Autodesk Fusion 360 part; units mm, degrees
(part 2 of 7)
  spline S34 degree 5 poles (70.565, 33.8524) (70.5561, 33.8452) (70.5384, 33.8307) (70.5118, 33.8091) (70.4765, 33.7801) (70.4325, 33.7437) (70.3887, 33.7072) (70.3451, 33.6706) (70.3016, 33.6339) (70.2583, 33.597) (70.2152, 33.56) (70.1723, 33.5229) (70.1295, 33.4857) (70.087, 33.4483) (70.0446, 33.4108) (70.0024, 33.3732) (69.9604, 33.3355) (69.9186, 33.2976) (69.8769, 33.2596) (69.8355, 33.2214) (69.7942, 33.1832) (69.7532, 33.1448) (69.7123, 33.1063) (69.6717, 33.0676) (69.6312, 33.0288) (69.591, 32.9899) (69.5509, 32.9509) (69.5111, 32.9117) (69.4714, 32.8724) (69.432, 32.8329) (69.3928, 32.7934) (69.3538, 32.7536) (69.315, 32.7138) (69.2765, 32.6738) (69.2381, 32.6337) (69.2, 32.5934) (69.1621, 32.553) (69.1245, 32.5124) (69.0871, 32.4717) (69.0499, 32.4309) (69.013, 32.3899) (68.9763, 32.3488) (68.9399, 32.3075) (68.9037, 32.2661) (68.8678, 32.2245) (68.8321, 32.1828) (68.7967, 32.1409) (68.7616, 32.0989) (68.7268, 32.0567) (68.6922, 32.0143) (68.658, 31.9718) (68.624, 31.9292) (68.5903, 31.8863) (68.5569, 31.8433) (68.5239, 31.8001) (68.4945, 31.7612) (68.4718, 31.7308) (68.4558, 31.7091) (68.4462, 31.696) (68.4431, 31.6918) knots -1 -1 -1 -1 -1 -1 -0.985714 -0.971429 -0.957143 -0.942857 -0.928571 -0.914286 -0.9 -0.885714 -0.871429 -0.857143 -0.842857 -0.828571 -0.814286 -0.8 -0.785714 -0.771429 -0.757143 -0.742857 -0.728571 -0.714286 -0.7 -0.685714 -0.671429 -0.657143 -0.642857 -0.628571 -0.614286 -0.6 -0.585714 -0.571429 -0.557143 -0.542857 -0.528571 -0.514286 -0.5 -0.485714 -0.471429 -0.457143 -0.442857 -0.428571 -0.414286 -0.4 -0.385714 -0.371429 -0.357143 -0.342857 -0.328571 -0.314286 -0.3 -0.285714 -0.271429 -0.257143 -0.242857 -0.228571 -0.221564 -0.221564 -0.221564 -0.221564 -0.221564 -0.221564
  spline S35 degree 3 poles (67.845, 31.5267) (67.905, 31.5013) (67.9693, 31.4879) (68.0995, 31.4866) (68.1641, 31.4986) (68.268, 31.54) (68.3088, 31.5632) (68.3827, 31.6204) (68.4155, 31.6541) (68.4431, 31.6918) knots 0 0 0 0 0.019532 0.019532 0.039064 0.039064 0.053081 0.053081 0.067098 0.067098 0.067098 0.067098
  arc A18 (67.845, 31.5267) -> (67.3814, 31.7187) centre (54.5011, -0.0327) ccw
  spline S36 degree 3 poles (67.0752, 32.2584) (67.0652, 32.194) (67.068, 32.1283) (67.0984, 32.0017) (67.1259, 31.942) (67.1914, 31.8514) (67.2239, 31.8175) (67.2974, 31.7599) (67.3381, 31.7363) (67.3814, 31.7187) knots 0 0 0 0 0.019532 0.019532 0.039064 0.039064 0.053081 0.053081 0.067098 0.067098 0.067098 0.067098
  spline S37 degree 5 poles (67.0752, 32.2584) (67.076, 32.2636) (67.0784, 32.2796) (67.0825, 32.3063) (67.0879, 32.3438) (67.0947, 32.3921) (67.1018, 32.446) (67.1086, 32.5) (67.1151, 32.5542) (67.1213, 32.6084) (67.1271, 32.6627) (67.1326, 32.717) (67.1378, 32.7715) (67.1427, 32.8261) (67.1473, 32.8807) (67.1516, 32.9354) (67.1556, 32.9902) (67.1593, 33.0451) (67.1627, 33.1) (67.1658, 33.155) (67.1687, 33.2101) (67.1713, 33.2653) (67.1736, 33.3205) (67.1757, 33.3758) (67.1775, 33.4312) (67.179, 33.4866) (67.1803, 33.5421) (67.1813, 33.5976) (67.1821, 33.6532) (67.1826, 33.7089) (67.1828, 33.7646) (67.1829, 33.8204) (67.1826, 33.8762) (67.1822, 33.9321) (67.1814, 33.988) (67.1805, 34.044) (67.1793, 34.1) (67.1779, 34.1561) (67.1762, 34.2122) (67.1743, 34.2684) (67.1722, 34.3246) (67.1699, 34.3809) (67.1673, 34.4372) (67.1645, 34.4935) (67.1615, 34.5499) (67.1583, 34.6064) (67.1548, 34.6628) (67.1511, 34.7194) (67.1472, 34.7759) (67.1431, 34.8325) (67.1388, 34.8892) (67.1343, 34.9458) (67.1295, 35.0025) (67.1245, 35.0593) (67.1194, 35.1161) (67.114, 35.1729) (67.1095, 35.2183) (67.106, 35.2525) (67.1037, 35.2752) (67.1025, 35.2866) knots 0.221564 0.221564 0.221564 0.221564 0.221564 0.221564 0.228571 0.242857 0.257143 0.271429 0.285714 0.3 0.314286 0.328571 0.342857 0.357143 0.371429 0.385714 0.4 0.414286 0.428571 0.442857 0.457143 0.471429 0.485714 0.5 0.514286 0.528571 0.542857 0.557143 0.571429 0.585714 0.6 0.614286 0.628571 0.642857 0.657143 0.671429 0.685714 0.7 0.714286 0.728571 0.742857 0.757143 0.771429 0.785714 0.8 0.814286 0.828571 0.842857 0.857143 0.871429 0.885714 0.9 0.914286 0.928571 0.942857 0.957143 0.971429 0.985714 1 1 1 1 1 1
  arc A19 (67.1025, 35.2866) -> (66.0047, 35.6593) centre (54.5011, -0.0327) ccw
  spline S38 degree 5 poles (66.0047, 35.6593) (65.9968, 35.651) (65.9811, 35.6343) (65.9576, 35.6094) (65.9264, 35.576) (65.8875, 35.5342) (65.8488, 35.4923) (65.8104, 35.4503) (65.7721, 35.4082) (65.734, 35.366) (65.6961, 35.3237) (65.6583, 35.2813) (65.6208, 35.2388) (65.5835, 35.1962) (65.5464, 35.1535) (65.5094, 35.1107) (65.4727, 35.0678) (65.4362, 35.0248) (65.3999, 34.9817) (65.3638, 34.9385) (65.3279, 34.8952) (65.2922, 34.8518) (65.2567, 34.8082) (65.2214, 34.7646) (65.1864, 34.7209) (65.1515, 34.677) (65.1169, 34.6331) (65.0825, 34.5891) (65.0484, 34.5449) (65.0144, 34.5007) (64.9807, 34.4563) (64.9472, 34.4118) (64.914, 34.3672) (64.881, 34.3226) (64.8482, 34.2778) (64.8157, 34.2329) (64.7834, 34.1879) (64.7514, 34.1428) (64.7196, 34.0975) (64.6881, 34.0522) (64.6568, 34.0067) (64.6259, 33.9612) (64.5951, 33.9155) (64.5647, 33.8697) (64.5345, 33.8238) (64.5046, 33.7778) (64.4749, 33.7316) (64.4456, 33.6854) (64.4166, 33.639) (64.3878, 33.5925) (64.3594, 33.5459) (64.3313, 33.4991) (64.3035, 33.4523) (64.276, 33.4053) (64.2489, 33.3581) (64.2248, 33.3157) (64.2063, 33.2826) (64.1933, 33.259) (64.1855, 33.2448) (64.1829, 33.2401) knots -1 -1 -1 -1 -1 -1 -0.985714 -0.971429 -0.957143 -0.942857 -0.928571 -0.914286 -0.9 -0.885714 -0.871429 -0.857143 -0.842857 -0.828571 -0.814286 -0.8 -0.785714 -0.771429 -0.757143 -0.742857 -0.728571 -0.714286 -0.7 -0.685714 -0.671429 -0.657143 -0.642857 -0.628571 -0.614286 -0.6 -0.585714 -0.571429 -0.557143 -0.542857 -0.528571 -0.514286 -0.5 -0.485714 -0.471429 -0.457143 -0.442857 -0.428571 -0.414286 -0.4 -0.385714 -0.371429 -0.357143 -0.342857 -0.328571 -0.314286 -0.3 -0.285714 -0.271429 -0.257143 -0.242857 -0.228571 -0.221564 -0.221564 -0.221564 -0.221564 -0.221564 -0.221564
  spline S39 degree 3 poles (63.6115, 32.9984) (63.6743, 32.9811) (63.7398, 32.9762) (63.8691, 32.9919) (63.9316, 33.0122) (64.0292, 33.0668) (64.0666, 33.0952) (64.1324, 33.1615) (64.1605, 33.1992) (64.1829, 33.2401) knots 0 0 0 0 0.019532 0.019532 0.039064 0.039064 0.053081 0.053081 0.067098 0.067098 0.067098 0.067098
  arc A20 (63.6115, 32.9984) -> (63.1268, 33.1283) centre (54.5011, -0.0327) ccw
  spline S40 degree 3 poles (62.7528, 33.6234) (62.7513, 33.5583) (62.7626, 33.4935) (62.8093, 33.372) (62.8443, 33.3164) (62.9211, 33.235) (62.9578, 33.2057) (63.0382, 33.1581) (63.0816, 33.1401) (63.1268, 33.1283) knots 0 0 0 0 0.019532 0.019532 0.039064 0.039064 0.053081 0.053081 0.067098 0.067098 0.067098 0.067098
  spline S41 degree 5 poles (62.7528, 33.6234) (62.7529, 33.6287) (62.7532, 33.6448) (62.7537, 33.6718) (62.7543, 33.7097) (62.7546, 33.7585) (62.7547, 33.8129) (62.7544, 33.8673) (62.7538, 33.9218) (62.7528, 33.9764) (62.7515, 34.031) (62.7498, 34.0856) (62.7479, 34.1403) (62.7456, 34.195) (62.743, 34.2498) (62.7401, 34.3046) (62.737, 34.3594) (62.7335, 34.4143) (62.7297, 34.4692) (62.7256, 34.5242) (62.7213, 34.5792) (62.7167, 34.6342) (62.7117, 34.6893) (62.7066, 34.7444) (62.7011, 34.7995) (62.6954, 34.8546) (62.6894, 34.9098) (62.6832, 34.965) (62.6767, 35.0202) (62.6699, 35.0755) (62.6629, 35.1307) (62.6556, 35.186) (62.6481, 35.2414) (62.6404, 35.2967) (62.6324, 35.3521) (62.6241, 35.4074) (62.6156, 35.4628) (62.6069, 35.5182) (62.5979, 35.5737) (62.5887, 35.6291) (62.5793, 35.6846) (62.5696, 35.7401) (62.5597, 35.7956) (62.5496, 35.8511) (62.5393, 35.9066) (62.5287, 35.9621) (62.5179, 36.0177) (62.5069, 36.0732) (62.4956, 36.1288) (62.4842, 36.1844) (62.4725, 36.24) (62.4606, 36.2955) (62.4484, 36.3511) (62.4361, 36.4068) (62.4236, 36.4624) (62.4108, 36.518) (62.4004, 36.5625) (62.3926, 36.5959) (62.3873, 36.6181) (62.3846, 36.6293) knots 0.221564 0.221564 0.221564 0.221564 0.221564 0.221564 0.228571 0.242857 0.257143 0.271429 0.285714 0.3 0.314286 0.328571 0.342857 0.357143 0.371429 0.385714 0.4 0.414286 0.428571 0.442857 0.457143 0.471429 0.485714 0.5 0.514286 0.528571 0.542857 0.557143 0.571429 0.585714 0.6 0.614286 0.628571 0.642857 0.657143 0.671429 0.685714 0.7 0.714286 0.728571 0.742857 0.757143 0.771429 0.785714 0.8 0.814286 0.828571 0.842857 0.857143 0.871429 0.885714 0.9 0.914286 0.928571 0.942857 0.957143 0.971429 0.985714 1 1 1 1 1 1
  arc A21 (62.3846, 36.6293) -> (61.2476, 36.8554) centre (54.5011, -0.0327) ccw
  spline S42 degree 5 poles (61.2476, 36.8554) (61.2408, 36.8462) (61.2274, 36.8276) (61.2074, 36.7998) (61.1808, 36.7627) (61.1477, 36.7162) (61.1148, 36.6696) (61.0821, 36.6229) (61.0497, 36.5762) (61.0174, 36.5294) (60.9853, 36.4825) (60.9535, 36.4355) (60.9218, 36.3885) (60.8904, 36.3414) (60.8591, 36.2942) (60.8281, 36.247) (60.7973, 36.1996) (60.7667, 36.1522) (60.7363, 36.1047) (60.7062, 36.0572) (60.6762, 36.0095) (60.6465, 35.9618) (60.617, 35.9141) (60.5877, 35.8662) (60.5587, 35.8183) (60.5299, 35.7703) (60.5013, 35.7222) (60.473, 35.674) (60.4449, 35.6258) (60.417, 35.5775) (60.3894, 35.5291) (60.362, 35.4806) (60.3348, 35.4321) (60.3079, 35.3835) (60.2813, 35.3348) (60.2549, 35.2861) (60.2288, 35.2372) (60.2029, 35.1883) (60.1773, 35.1393) (60.152, 35.0903) (60.1269, 35.0411) (60.1021, 34.9919) (60.0776, 34.9426) (60.0534, 34.8932) (60.0295, 34.8438) (60.0058, 34.7942) (59.9825, 34.7446) (59.9594, 34.6949) (59.9367, 34.6452) (59.9143, 34.5953) (59.8922, 34.5454) (59.8704, 34.4954) (59.849, 34.4453) (59.8279, 34.3951) (59.8071, 34.3448) (59.7888, 34.2996) (59.7748, 34.2644) (59.7649, 34.2392) (59.759, 34.2242) (59.7571, 34.2192) knots -1 -1 -1 -1 -1 -1 -0.985714 -0.971429 -0.957143 -0.942857 -0.928571 -0.914286 -0.9 -0.885714 -0.871429 -0.857143 -0.842857 -0.828571 -0.814286 -0.8 -0.785714 -0.771429 -0.757143 -0.742857 -0.728571 -0.714286 -0.7 -0.685714 -0.671429 -0.657143 -0.642857 -0.628571 -0.614286 -0.6 -0.585714 -0.571429 -0.557143 -0.542857 -0.528571 -0.514286 -0.5 -0.485714 -0.471429 -0.457143 -0.442857 -0.428571 -0.414286 -0.4 -0.385714 -0.371429 -0.357143 -0.342857 -0.328571 -0.314286 -0.3 -0.285714 -0.271429 -0.257143 -0.242857 -0.228571 -0.221564 -0.221564 -0.221564 -0.221564 -0.221564 -0.221564
  spline S43 degree 3 poles (59.2221, 33.905) (59.2866, 33.896) (59.3522, 33.8997) (59.4784, 33.9321) (59.5377, 33.9605) (59.6273, 34.0273) (59.6607, 34.0603) (59.7173, 34.1347) (59.7402, 34.1757) (59.7571, 34.2192) knots 0 0 0 0 0.019532 0.019532 0.039064 0.039064 0.053081 0.053081 0.067098 0.067098 0.067098 0.067098
  arc A22 (59.2221, 33.905) -> (58.7246, 33.9705) centre (54.5011, -0.0327) ccw
  spline S44 degree 3 poles (58.2892, 34.4125) (58.2962, 34.3478) (58.3159, 34.285) (58.3781, 34.1706) (58.42, 34.1201) (58.5068, 34.0495) (58.547, 34.0252) (58.6329, 33.9885) (58.6782, 33.9763) (58.7246, 33.9705) knots 0 0 0 0 0.019532 0.019532 0.039064 0.039064 0.053081 0.053081 0.067098 0.067098 0.067098 0.067098
  spline S45 degree 5 poles (58.2892, 34.4125) (58.2886, 34.4178) (58.2868, 34.4338) (58.2838, 34.4607) (58.2794, 34.4983) (58.2734, 34.5467) (58.2663, 34.6007) (58.2589, 34.6546) (58.2512, 34.7085) (58.2431, 34.7625) (58.2347, 34.8164) (58.2259, 34.8704) (58.2169, 34.9244) (58.2075, 34.9783) (58.1978, 35.0323) (58.1877, 35.0862) (58.1774, 35.1402) (58.1668, 35.1942) (58.1559, 35.2481) (58.1447, 35.3021) (58.1332, 35.356) (58.1214, 35.41) (58.1094, 35.4639) (58.0971, 35.5179) (58.0845, 35.5718) (58.0716, 35.6257) (58.0585, 35.6797) (58.0451, 35.7336) (58.0314, 35.7875) (58.0175, 35.8414) (58.0033, 35.8952) (57.9889, 35.9491) (57.9742, 36.003) (57.9593, 36.0568) (57.9442, 36.1107) (57.9288, 36.1645) (57.9131, 36.2183) (57.8972, 36.2721) (57.8811, 36.3259) (57.8647, 36.3797) (57.8482, 36.4334) (57.8313, 36.4872) (57.8143, 36.5409) (57.797, 36.5946) (57.7795, 36.6483) (57.7617, 36.702) (57.7438, 36.7557) (57.7256, 36.8093) (57.7072, 36.8629) (57.6886, 36.9165) (57.6697, 36.9701) (57.6507, 37.0237) (57.6314, 37.0772) (57.6119, 37.1307) (57.5922, 37.1842) (57.5723, 37.2377) (57.5562, 37.2805) (57.5441, 37.3126) (57.5359, 37.3339) (57.5318, 37.3446) knots 0.221564 0.221564 0.221564 0.221564 0.221564 0.221564 0.228571 0.242857 0.257143 0.271429 0.285714 0.3 0.314286 0.328571 0.342857 0.357143 0.371429 0.385714 0.4 0.414286 0.428571 0.442857 0.457143 0.471429 0.485714 0.5 0.514286 0.528571 0.542857 0.557143 0.571429 0.585714 0.6 0.614286 0.628571 0.642857 0.657143 0.671429 0.685714 0.7 0.714286 0.728571 0.742857 0.757143 0.771429 0.785714 0.8 0.814286 0.828571 0.842857 0.857143 0.871429 0.885714 0.9 0.914286 0.928571 0.942857 0.957143 0.971429 0.985714 1 1 1 1 1 1
  arc A23 (57.5318, 37.3446) -> (56.375, 37.4204) centre (54.5011, -0.0327) ccw
  spline S46 degree 5 poles (56.375, 37.4204) (56.3695, 37.4104) (56.3586, 37.3903) (56.3424, 37.3601) (56.3209, 37.3198) (56.2941, 37.2693) (56.2676, 37.2189) (56.2413, 37.1683) (56.2152, 37.1178) (56.1893, 37.0671) (56.1637, 37.0165) (56.1382, 36.9658) (56.113, 36.915) (56.0879, 36.8642) (56.0631, 36.8133) (56.0385, 36.7624) (56.0142, 36.7115) (55.99, 36.6605) (55.9661, 36.6094) (55.9424, 36.5584) (55.9189, 36.5072) (55.8957, 36.456) (55.8727, 36.4048) (55.8499, 36.3535) (55.8274, 36.3022) (55.8051, 36.2509) (55.783, 36.1995) (55.7612, 36.148) (55.7396, 36.0965) (55.7183, 36.045) (55.6972, 35.9934) (55.6764, 35.9418) (55.6558, 35.8902) (55.6355, 35.8385) (55.6155, 35.7867) (55.5957, 35.7349) (55.5761, 35.6831) (55.5569, 35.6312) (55.5379, 35.5793) (55.5192, 35.5274) (55.5007, 35.4754) (55.4826, 35.4233) (55.4647, 35.3713) (55.4472, 35.3192) (55.4299, 35.267) (55.4129, 35.2148) (55.3962, 35.1626) (55.3799, 35.1103) (55.3638, 35.058) (55.3481, 35.0056) (55.3327, 34.9532) (55.3177, 34.9008) (55.3029, 34.8483) (55.2886, 34.7958) (55.2745, 34.7433) (55.2623, 34.6961) (55.253, 34.6593) (55.2465, 34.6331) (55.2426, 34.6174) (55.2414, 34.6122) knots -1 -1 -1 -1 -1 -1 -0.985714 -0.971429 -0.957143 -0.942857 -0.928571 -0.914286 -0.9 -0.885714 -0.871429 -0.857143 -0.842857 -0.828571 -0.814286 -0.8 -0.785714 -0.771429 -0.757143 -0.742857 -0.728571 -0.714286 -0.7 -0.685714 -0.671429 -0.657143 -0.642857 -0.628571 -0.614286 -0.6 -0.585714 -0.571429 -0.557143 -0.542857 -0.528571 -0.514286 -0.5 -0.485714 -0.471429 -0.457143 -0.442857 -0.428571 -0.414286 -0.4 -0.385714 -0.371429 -0.357143 -0.342857 -0.328571 -0.314286 -0.3 -0.285714 -0.271429 -0.257143 -0.242857 -0.228571 -0.221564 -0.221564 -0.221564 -0.221564 -0.221564 -0.221564
  spline S47 degree 3 poles (54.752, 34.2309) (54.8171, 34.2304) (54.8817, 34.2426) (55.0025, 34.2912) (55.0576, 34.327) (55.1378, 34.405) (55.1665, 34.4421) (55.2129, 34.5232) (55.2303, 34.5669) (55.2414, 34.6122) knots 0 0 0 0 0.019532 0.019532 0.039064 0.039064 0.053081 0.053081 0.067098 0.067098 0.067098 0.067098
  arc A24 (54.752, 34.2309) -> (54.2502, 34.2309) centre (54.5011, -0.0327) ccw
  spline S48 degree 3 poles (53.7608, 34.6122) (53.7762, 34.549) (53.8039, 34.4894) (53.8805, 34.3841) (53.9287, 34.3394) (54.0239, 34.2807) (54.0669, 34.2619) (54.1569, 34.2367) (54.2034, 34.2305) (54.2502, 34.2309) knots 0 0 0 0 0.019532 0.019532 0.039064 0.039064 0.053081 0.053081 0.067098 0.067098 0.067098 0.067098
  spline S49 degree 5 poles (53.7608, 34.6122) (53.7595, 34.6174) (53.7557, 34.6331) (53.7492, 34.6593) (53.7399, 34.6961) (53.7276, 34.7433) (53.7136, 34.7958) (53.6992, 34.8483) (53.6845, 34.9008) (53.6694, 34.9532) (53.654, 35.0056) (53.6383, 35.058) (53.6223, 35.1103) (53.6059, 35.1626) (53.5892, 35.2148) (53.5723, 35.267) (53.555, 35.3192) (53.5374, 35.3713) (53.5195, 35.4233) (53.5014, 35.4754) (53.483, 35.5274) (53.4643, 35.5793) (53.4453, 35.6312) (53.426, 35.6831) (53.4065, 35.7349) (53.3867, 35.7867) (53.3666, 35.8385) (53.3463, 35.8902) (53.3257, 35.9418) (53.3049, 35.9934) (53.2838, 36.045) (53.2625, 36.0965) (53.2409, 36.148) (53.2191, 36.1995) (53.1971, 36.2509) (53.1748, 36.3022) (53.1522, 36.3535) (53.1294, 36.4048) (53.1064, 36.456) (53.0832, 36.5072) (53.0597, 36.5584) (53.036, 36.6094) (53.0121, 36.6605) (52.988, 36.7115) (52.9636, 36.7624) (52.939, 36.8133) (52.9142, 36.8642) (52.8892, 36.915) (52.8639, 36.9658) (52.8385, 37.0165) (52.8128, 37.0671) (52.7869, 37.1178) (52.7608, 37.1683) (52.7345, 37.2189) (52.708, 37.2693) (52.6813, 37.3198) (52.6597, 37.3601) (52.6435, 37.3903) (52.6326, 37.4104) (52.6272, 37.4204) knots 0.221564 0.221564 0.221564 0.221564 0.221564 0.221564 0.228571 0.242857 0.257143 0.271429 0.285714 0.3 0.314286 0.328571 0.342857 0.357143 0.371429 0.385714 0.4 0.414286 0.428571 0.442857 0.457143 0.471429 0.485714 0.5 0.514286 0.528571 0.542857 0.557143 0.571429 0.585714 0.6 0.614286 0.628571 0.642857 0.657143 0.671429 0.685714 0.7 0.714286 0.728571 0.742857 0.757143 0.771429 0.785714 0.8 0.814286 0.828571 0.842857 0.857143 0.871429 0.885714 0.9 0.914286 0.928571 0.942857 0.957143 0.971429 0.985714 1 1 1 1 1 1
  arc A25 (52.6272, 37.4204) -> (51.4703, 37.3446) centre (54.5011, -0.0327) ccw
  spline S50 degree 5 poles (51.4703, 37.3446) (51.4662, 37.3339) (51.4581, 37.3126) (51.4459, 37.2805) (51.4298, 37.2377) (51.4099, 37.1842) (51.3902, 37.1307) (51.3707, 37.0772) (51.3515, 37.0237) (51.3324, 36.9701) (51.3136, 36.9165) (51.2949, 36.8629) (51.2765, 36.8093) (51.2584, 36.7557) (51.2404, 36.702) (51.2227, 36.6483) (51.2052, 36.5946) (51.1879, 36.5409) (51.1708, 36.4872) (51.154, 36.4334) (51.1374, 36.3797) (51.121, 36.3259) (51.1049, 36.2721) (51.089, 36.2183) (51.0734, 36.1645) (51.058, 36.1107) (51.0428, 36.0568) (51.0279, 36.003) (51.0132, 35.9491) (50.9988, 35.8952) (50.9846, 35.8414) (50.9707, 35.7875) (50.9571, 35.7336) (50.9437, 35.6797) (50.9306, 35.6257) (50.9177, 35.5718) (50.9051, 35.5179) (50.8928, 35.4639) (50.8807, 35.41) (50.8689, 35.356) (50.8575, 35.3021) (50.8463, 35.2481) (50.8353, 35.1942) (50.8247, 35.1402) (50.8144, 35.0862) (50.8044, 35.0323) (50.7947, 34.9783) (50.7853, 34.9244) (50.7762, 34.8704) (50.7675, 34.8164) (50.759, 34.7625) (50.7509, 34.7085) (50.7432, 34.6546) (50.7358, 34.6007) (50.7287, 34.5467) (50.7228, 34.4983) (50.7183, 34.4607) (50.7153, 34.4338) (50.7135, 34.4178) (50.713, 34.4125) knots -1 -1 -1 -1 -1 -1 -0.985714 -0.971429 -0.957143 -0.942857 -0.928571 -0.914286 -0.9 -0.885714 -0.871429 -0.857143 -0.842857 -0.828571 -0.814286 -0.8 -0.785714 -0.771429 -0.757143 -0.742857 -0.728571 -0.714286 -0.7 -0.685714 -0.671429 -0.657143 -0.642857 -0.628571 -0.614286 -0.6 -0.585714 -0.571429 -0.557143 -0.542857 -0.528571 -0.514286 -0.5 -0.485714 -0.471429 -0.457143 -0.442857 -0.428571 -0.414286 -0.4 -0.385714 -0.371429 -0.357143 -0.342857 -0.328571 -0.314286 -0.3 -0.285714 -0.271429 -0.257143 -0.242857 -0.228571 -0.221564 -0.221564 -0.221564 -0.221564 -0.221564 -0.221564
  spline S51 degree 3 poles (50.2775, 33.9705) (50.3422, 33.9785) (50.4046, 33.9991) (50.518, 34.063) (50.568, 34.1057) (50.6373, 34.1935) (50.661, 34.234) (50.6964, 34.3205) (50.7079, 34.366) (50.713, 34.4125) knots 0 0 0 0 0.019532 0.019532 0.039064 0.039064 0.053081 0.053081 0.067098 0.067098 0.067098 0.067098
  arc A26 (50.2775, 33.9705) -> (49.78, 33.905) centre (54.5011, -0.0327) ccw
  spline S52 degree 3 poles (49.245, 34.2192) (49.2686, 34.1585) (49.3038, 34.103) (49.3935, 34.0086) (49.4471, 33.9706) (49.5492, 33.9249) (49.5943, 33.9118) (49.6868, 33.8986) (49.7337, 33.8986) (49.78, 33.905) knots 0 0 0 0 0.019532 0.019532 0.039064 0.039064 0.053081 0.053081 0.067098 0.067098 0.067098 0.067098
  spline S53 degree 5 poles (49.245, 34.2192) (49.2431, 34.2242) (49.2372, 34.2392) (49.2274, 34.2644) (49.2134, 34.2996) (49.195, 34.3448) (49.1743, 34.3951) (49.1532, 34.4453) (49.1317, 34.4954) (49.1099, 34.5454) (49.0878, 34.5953) (49.0654, 34.6452) (49.0427, 34.6949) (49.0197, 34.7446) (48.9963, 34.7942) (48.9727, 34.8438) (48.9487, 34.8932) (48.9245, 34.9426) (48.9, 34.9919) (48.8752, 35.0411) (48.8502, 35.0903) (48.8248, 35.1393) (48.7992, 35.1883) (48.7734, 35.2372) (48.7472, 35.2861) (48.7208, 35.3348) (48.6942, 35.3835) (48.6673, 35.4321) (48.6402, 35.4806) (48.6128, 35.5291) (48.5852, 35.5775) (48.5573, 35.6258) (48.5292, 35.674) (48.5008, 35.7222) (48.4723, 35.7703) (48.4434, 35.8183) (48.4144, 35.8662) (48.3851, 35.9141) (48.3556, 35.9618) (48.3259, 36.0095) (48.296, 36.0572) (48.2658, 36.1047) (48.2354, 36.1522) (48.2048, 36.1996) (48.174, 36.247) (48.143, 36.2942) (48.1118, 36.3414) (48.0803, 36.3885) (48.0487, 36.4355) (48.0168, 36.4825) (47.9847, 36.5294) (47.9525, 36.5762) (47.92, 36.6229) (47.8873, 36.6696) (47.8544, 36.7162) (47.8214, 36.7627) (47.7948, 36.7998) (47.7747, 36.8276) (47.7613, 36.8462) (47.7546, 36.8554) knots 0.221564 0.221564 0.221564 0.221564 0.221564 0.221564 0.228571 0.242857 0.257143 0.271429 0.285714 0.3 0.314286 0.328571 0.342857 0.357143 0.371429 0.385714 0.4 0.414286 0.428571 0.442857 0.457143 0.471429 0.485714 0.5 0.514286 0.528571 0.542857 0.557143 0.571429 0.585714 0.6 0.614286 0.628571 0.642857 0.657143 0.671429 0.685714 0.7 0.714286 0.728571 0.742857 0.757143 0.771429 0.785714 0.8 0.814286 0.828571 0.842857 0.857143 0.871429 0.885714 0.9 0.914286 0.928571 0.942857 0.957143 0.971429 0.985714 1 1 1 1 1 1
  arc A27 (47.7546, 36.8554) -> (46.6175, 36.6293) centre (54.5011, -0.0327) ccw
  spline S54 degree 5 poles (46.6175, 36.6293) (46.6149, 36.6181) (46.6096, 36.5959) (46.6017, 36.5625) (46.5913, 36.518) (46.5786, 36.4624) (46.566, 36.4068) (46.5537, 36.3511) (46.5416, 36.2955) (46.5297, 36.24) (46.518, 36.1844) (46.5065, 36.1288) (46.4953, 36.0732) (46.4843, 36.0177) (46.4735, 35.9621) (46.4629, 35.9066) (46.4525, 35.8511) (46.4424, 35.7956) (46.4325, 35.7401) (46.4228, 35.6846) (46.4134, 35.6291) (46.4042, 35.5737) (46.3952, 35.5182) (46.3865, 35.4628) (46.378, 35.4074) (46.3698, 35.3521) (46.3618, 35.2967) (46.354, 35.2414) (46.3465, 35.186) (46.3392, 35.1307) (46.3322, 35.0755) (46.3255, 35.0202) (46.319, 34.965) (46.3127, 34.9098) (46.3067, 34.8546) (46.301, 34.7995) (46.2956, 34.7444) (46.2904, 34.6893) (46.2855, 34.6342) (46.2809, 34.5792) (46.2765, 34.5242) (46.2725, 34.4692) (46.2687, 34.4143) (46.2652, 34.3594) (46.262, 34.3046) (46.2591, 34.2498) (46.2565, 34.195) (46.2543, 34.1403) (46.2523, 34.0856) (46.2507, 34.031) (46.2494, 33.9764) (46.2484, 33.9218) (46.2477, 33.8673) (46.2474, 33.8129) (46.2475, 33.7585) (46.2479, 33.7097) (46.2484, 33.6718) (46.2489, 33.6448) (46.2493, 33.6287) (46.2494, 33.6234) knots -1 -1 -1 -1 -1 -1 -0.985714 -0.971429 -0.957143 -0.942857 -0.928571 -0.914286 -0.9 -0.885714 -0.871429 -0.857143 -0.842857 -0.828571 -0.814286 -0.8 -0.785714 -0.771429 -0.757143 -0.742857 -0.728571 -0.714286 -0.7 -0.685714 -0.671429 -0.657143 -0.642857 -0.628571 -0.614286 -0.6 -0.585714 -0.571429 -0.557143 -0.542857 -0.528571 -0.514286 -0.5 -0.485714 -0.471429 -0.457143 -0.442857 -0.428571 -0.414286 -0.4 -0.385714 -0.371429 -0.357143 -0.342857 -0.328571 -0.314286 -0.3 -0.285714 -0.271429 -0.257143 -0.242857 -0.228571 -0.221564 -0.221564 -0.221564 -0.221564 -0.221564 -0.221564
  spline S55 degree 3 poles (45.8754, 33.1283) (45.9384, 33.1447) (45.9976, 33.1732) (46.1017, 33.2514) (46.1457, 33.3003) (46.2029, 33.3964) (46.2211, 33.4397) (46.2449, 33.53) (46.2504, 33.5766) (46.2494, 33.6234) knots 0 0 0 0 0.019532 0.019532 0.039064 0.039064 0.053081 0.053081 0.067098 0.067098 0.067098 0.067098
  arc A28 (45.8754, 33.1283) -> (45.3906, 32.9984) centre (54.5011, -0.0327) ccw
  spline S56 degree 3 poles (44.8192, 33.2401) (44.8505, 33.1831) (44.8927, 33.1326) (44.9939, 33.0507) (45.052, 33.0201) (45.1592, 32.988) (45.2056, 32.981) (45.299, 32.98) (45.3456, 32.986) (45.3906, 32.9984) knots 0 0 0 0 0.019532 0.019532 0.039064 0.039064 0.053081 0.053081 0.067098 0.067098 0.067098 0.067098
  spline S57 degree 5 poles (44.8192, 33.2401) (44.8167, 33.2448) (44.8089, 33.259) (44.7958, 33.2826) (44.7773, 33.3157) (44.7533, 33.3581) (44.7261, 33.4053) (44.6986, 33.4523) (44.6708, 33.4991) (44.6427, 33.5459) (44.6143, 33.5925) (44.5856, 33.639) (44.5565, 33.6854) (44.5272, 33.7316) (44.4976, 33.7778) (44.4677, 33.8238) (44.4375, 33.8697) (44.407, 33.9155) (44.3763, 33.9612) (44.3453, 34.0067) (44.314, 34.0522) (44.2825, 34.0975) (44.2507, 34.1428) (44.2187, 34.1879) (44.1864, 34.2329) (44.1539, 34.2778) (44.1211, 34.3226) (44.0881, 34.3672) (44.0549, 34.4118) (44.0214, 34.4563) (43.9877, 34.5007) (43.9538, 34.5449) (43.9196, 34.5891) (43.8852, 34.6331) (43.8506, 34.677) (43.8158, 34.7209) (43.7807, 34.7646) (43.7455, 34.8082) (43.71, 34.8518) (43.6743, 34.8952) (43.6384, 34.9385) (43.6023, 34.9817) (43.566, 35.0248) (43.5294, 35.0678) (43.4927, 35.1107) (43.4558, 35.1535) (43.4187, 35.1962) (43.3813, 35.2388) (43.3438, 35.2813) (43.3061, 35.3237) (43.2682, 35.366) (43.2301, 35.4082) (43.1918, 35.4503) (43.1533, 35.4923) (43.1146, 35.5342) (43.0758, 35.576) (43.0445, 35.6094) (43.021, 35.6343) (43.0053, 35.651) (42.9974, 35.6593) knots 0.221564 0.221564 0.221564 0.221564 0.221564 0.221564 0.228571 0.242857 0.257143 0.271429 0.285714 0.3 0.314286 0.328571 0.342857 0.357143 0.371429 0.385714 0.4 0.414286 0.428571 0.442857 0.457143 0.471429 0.485714 0.5 0.514286 0.528571 0.542857 0.557143 0.571429 0.585714 0.6 0.614286 0.628571 0.642857 0.657143 0.671429 0.685714 0.7 0.714286 0.728571 0.742857 0.757143 0.771429 0.785714 0.8 0.814286 0.828571 0.842857 0.857143 0.871429 0.885714 0.9 0.914286 0.928571 0.942857 0.957143 0.971429 0.985714 1 1 1 1 1 1
  arc A29 (42.9974, 35.6593) -> (41.8996, 35.2866) centre (54.5011, -0.0327) ccw
  spline S58 degree 5 poles (41.8996, 35.2866) (41.8984, 35.2752) (41.8961, 35.2525) (41.8926, 35.2183) (41.8882, 35.1729) (41.8828, 35.1161) (41.8776, 35.0593) (41.8726, 35.0025) (41.8679, 34.9458) (41.8633, 34.8892) (41.859, 34.8325) (41.8549, 34.7759) (41.851, 34.7194) (41.8473, 34.6628) (41.8439, 34.6064) (41.8406, 34.5499) (41.8376, 34.4935) (41.8348, 34.4372) (41.8322, 34.3809) (41.8299, 34.3246) (41.8278, 34.2684) (41.8259, 34.2122) (41.8243, 34.1561) (41.8228, 34.1) (41.8216, 34.044) (41.8207, 33.988) (41.82, 33.9321) (41.8195, 33.8762) (41.8193, 33.8204) (41.8193, 33.7646) (41.8196, 33.7089) (41.8201, 33.6532) (41.8208, 33.5976) (41.8219, 33.5421) (41.8231, 33.4866) (41.8247, 33.4312) (41.8265, 33.3758) (41.8285, 33.3205) (41.8308, 33.2653) (41.8334, 33.2101) (41.8363, 33.155) (41.8394, 33.1) (41.8429, 33.0451) (41.8466, 32.9902) (41.8506, 32.9354) (41.8549, 32.8807) (41.8594, 32.8261) (41.8643, 32.7715) (41.8695, 32.717) (41.8751, 32.6627) (41.8809, 32.6084) (41.887, 32.5542) (41.8935, 32.5) (41.9003, 32.446) (41.9075, 32.3921) (41.9142, 32.3438) (41.9197, 32.3063) (41.9237, 32.2796) (41.9262, 32.2636) (41.927, 32.2584) knots -1 -1 -1 -1 -1 -1 -0.985714 -0.971429 -0.957143 -0.942857 -0.928571 -0.914286 -0.9 -0.885714 -0.871429 -0.857143 -0.842857 -0.828571 -0.814286 -0.8 -0.785714 -0.771429 -0.757143 -0.742857 -0.728571 -0.714286 -0.7 -0.685714 -0.671429 -0.657143 -0.642857 -0.628571 -0.614286 -0.6 -0.585714 -0.571429 -0.557143 -0.542857 -0.528571 -0.514286 -0.5 -0.485714 -0.471429 -0.457143 -0.442857 -0.428571 -0.414286 -0.4 -0.385714 -0.371429 -0.357143 -0.342857 -0.328571 -0.314286 -0.3 -0.285714 -0.271429 -0.257143 -0.242857 -0.228571 -0.221564 -0.221564 -0.221564 -0.221564 -0.221564 -0.221564
  spline S59 degree 3 poles (41.6208, 31.7187) (41.6811, 31.7432) (41.7361, 31.7792) (41.8291, 31.8703) (41.8663, 31.9245) (41.9105, 32.0272) (41.9229, 32.0725) (41.9347, 32.1652) (41.9341, 32.2122) (41.927, 32.2584) knots 0 0 0 0 0.019532 0.019532 0.039064 0.039064 0.053081 0.053081 0.067098 0.067098 0.067098 0.067098
  arc A30 (41.6208, 31.7187) -> (41.1571, 31.5267) centre (54.5011, -0.0327) ccw
  spline S60 degree 3 poles (40.5591, 31.6918) (40.5975, 31.6392) (40.6459, 31.5947) (40.757, 31.5268) (40.8186, 31.5039) (40.929, 31.4862) (40.976, 31.4852) (41.0687, 31.4964) (41.1141, 31.5085) (41.1571, 31.5267) knots 0 0 0 0 0.019532 0.019532 0.039064 0.039064 0.053081 0.053081 0.067098 0.067098 0.067098 0.067098
  spline S61 degree 5 poles (40.5591, 31.6918) (40.5559, 31.696) (40.5464, 31.7091) (40.5303, 31.7308) (40.5077, 31.7612) (40.4783, 31.8001) (40.4452, 31.8433) (40.4118, 31.8863) (40.3782, 31.9292) (40.3442, 31.9718) (40.3099, 32.0143) (40.2754, 32.0567) (40.2405, 32.0989) (40.2054, 32.1409) (40.17, 32.1828) (40.1344, 32.2245) (40.0984, 32.2661) (40.0623, 32.3075) (40.0258, 32.3488) (39.9891, 32.3899) (39.9522, 32.4309) (39.915, 32.4717) (39.8776, 32.5124) (39.84, 32.553) (39.8021, 32.5934) (39.764, 32.6337) (39.7257, 32.6738) (39.6871, 32.7138) (39.6483, 32.7536) (39.6094, 32.7934) (39.5701, 32.8329) (39.5307, 32.8724) (39.4911, 32.9117) (39.4512, 32.9509) (39.4112, 32.9899) (39.3709, 33.0288) (39.3305, 33.0676) (39.2898, 33.1063) (39.249, 33.1448) (39.2079, 33.1832) (39.1667, 33.2214) (39.1252, 33.2596) (39.0836, 33.2976) (39.0418, 33.3355) (38.9997, 33.3732) (38.9575, 33.4108) (38.9152, 33.4483) (38.8726, 33.4857) (38.8298, 33.5229) (38.7869, 33.56) (38.7438, 33.597) (38.7005, 33.6339) (38.6571, 33.6706) (38.6134, 33.7072) (38.5696, 33.7437) (38.5256, 33.7801) (38.4903, 33.8091) (38.4637, 33.8307) (38.446, 33.8452) (38.4371, 33.8524) knots 0.221564 0.221564 0.221564 0.221564 0.221564 0.221564 0.228571 0.242857 0.257143 0.271429 0.285714 0.3 0.314286 0.328571 0.342857 0.357143 0.371429 0.385714 0.4 0.414286 0.428571 0.442857 0.457143 0.471429 0.485714 0.5 0.514286 0.528571 0.542857 0.557143 0.571429 0.585714 0.6 0.614286 0.628571 0.642857 0.657143 0.671429 0.685714 0.7 0.714286 0.728571 0.742857 0.757143 0.771429 0.785714 0.8 0.814286 0.828571 0.842857 0.857143 0.871429 0.885714 0.9 0.914286 0.928571 0.942857 0.957143 0.971429 0.985714 1 1 1 1 1 1
  arc A31 (38.4371, 33.8524) -> (37.3973, 33.3396) centre (54.5011, -0.0327) ccw
  spline S62 degree 5 poles (37.3973, 33.3396) (37.3977, 33.3282) (37.3983, 33.3053) (37.3993, 33.271) (37.4008, 33.2254) (37.4029, 33.1683) (37.4052, 33.1114) (37.4077, 33.0545) (37.4103, 32.9976) (37.4132, 32.9408) (37.4163, 32.8841) (37.4196, 32.8275) (37.4232, 32.7709) (37.4269, 32.7144) (37.4308, 32.6579) (37.435, 32.6016) (37.4394, 32.5452) (37.444, 32.489) (37.4488, 32.4328) (37.4538, 32.3768) (37.459, 32.3207) (37.4645, 32.2648) (37.4702, 32.2089) (37.4761, 32.1531) (37.4822, 32.0974) (37.4886, 32.0418) (37.4952, 31.9863) (37.502, 31.9308) (37.5091, 31.8754) (37.5164, 31.8201) (37.5239, 31.7649) (37.5317, 31.7098) (37.5397, 31.6548) (37.5479, 31.5999) (37.5564, 31.545) (37.5652, 31.4903) (37.5742, 31.4356) (37.5835, 31.3811) (37.593, 31.3266) (37.6027, 31.2723) (37.6128, 31.218) (37.6231, 31.1639) (37.6336, 31.1099) (37.6445, 31.0559) (37.6556, 31.0021) (37.667, 30.9484) (37.6787, 30.8949) (37.6906, 30.8414) (37.7029, 30.7881) (37.7155, 30.7349) (37.7283, 30.6818) (37.7415, 30.6289) (37.755, 30.5761) (37.7688, 30.5234) (37.7829, 30.4709) (37.7959, 30.4239) (37.8062, 30.3874) (37.8137, 30.3615) (37.8182, 30.346) (37.8197, 30.3409) knots -1 -1 -1 -1 -1 -1 -0.985714 -0.971429 -0.957143 -0.942857 -0.928571 -0.914286 -0.9 -0.885714 -0.871429 -0.857143 -0.842857 -0.828571 -0.814286 -0.8 -0.785714 -0.771429 -0.757143 -0.742857 -0.728571 -0.714286 -0.7 -0.685714 -0.671429 -0.657143 -0.642857 -0.628571 -0.614286 -0.6 -0.585714 -0.571429 -0.557143 -0.542857 -0.528571 -0.514286 -0.5 -0.485714 -0.471429 -0.457143 -0.442857 -0.428571 -0.414286 -0.4 -0.385714 -0.371429 -0.357143 -0.342857 -0.328571 -0.314286 -0.3 -0.285714 -0.271429 -0.257143 -0.242857 -0.228571 -0.221564 -0.221564 -0.221564 -0.221564 -0.221564 -0.221564
  spline S63 degree 3 poles (37.5866, 29.7659) (37.6432, 29.798) (37.693, 29.8409) (37.7734, 29.9434) (37.8032, 30.002) (37.8336, 30.1096) (37.8399, 30.1561) (37.8396, 30.2495) (37.8328, 30.296) (37.8197, 30.3409) knots 0 0 0 0 0.019532 0.019532 0.039064 0.039064 0.053081 0.053081 0.067098 0.067098 0.067098 0.067098
  arc A32 (37.5866, 29.7659) -> (37.152, 29.515) centre (54.5011, -0.0327) ccw
  spline S64 degree 3 poles (36.5375, 29.6006) (36.5825, 29.5535) (36.6362, 29.5157) (36.7552, 29.4628) (36.8193, 29.4482) (36.9311, 29.445) (36.9778, 29.4502) (37.0683, 29.4734) (37.1117, 29.4913) (37.152, 29.515) knots 0 0 0 0 0.019532 0.019532 0.039064 0.039064 0.053081 0.053081 0.067098 0.067098 0.067098 0.067098
  spline S65 degree 5 poles (36.5375, 29.6006) (36.5338, 29.6044) (36.5226, 29.6161) (36.5039, 29.6355) (36.4775, 29.6627) (36.4432, 29.6975) (36.4048, 29.7359) (36.3661, 29.7742) (36.3271, 29.8123) (36.2879, 29.8502) (36.2483, 29.8879) (36.2085, 29.9253) (36.1685, 29.9626) (36.1282, 29.9997) (36.0876, 30.0366) (36.0468, 30.0733) (36.0058, 30.1099) (35.9645, 30.1462) (35.923, 30.1824) (35.8813, 30.2184) (35.8393, 30.2542) (35.7971, 30.2898) (35.7548, 30.3253) (35.7121, 30.3606) (35.6693, 30.3957) (35.6263, 30.4306) (35.583, 30.4654) (35.5396, 30.5) (35.4959, 30.5345) (35.4521, 30.5688) (35.4081, 30.6029) (35.3638, 30.6369) (35.3194, 30.6707) (35.2748, 30.7043) (35.23, 30.7378) (35.185, 30.7711) (35.1398, 30.8043) (35.0944, 30.8373) (35.0489, 30.8702) (35.0032, 30.9029) (34.9573, 30.9354) (34.9112, 30.9678) (34.865, 31) (34.8186, 31.0321) (34.772, 31.0641) (34.7253, 31.0959) (34.6784, 31.1275) (34.6313, 31.159) (34.584, 31.1903) (34.5366, 31.2215) (34.4891, 31.2526) (34.4413, 31.2835) (34.3934, 31.3142) (34.3454, 31.3448) (34.2972, 31.3753) (34.2489, 31.4056) (34.2101, 31.4297) (34.1809, 31.4477) (34.1614, 31.4597) (34.1517, 31.4657) knots 0.221564 0.221564 0.221564 0.221564 0.221564 0.221564 0.228571 0.242857 0.257143 0.271429 0.285714 0.3 0.314286 0.328571 0.342857 0.357143 0.371429 0.385714 0.4 0.414286 0.428571 0.442857 0.457143 0.471429 0.485714 0.5 0.514286 0.528571 0.542857 0.557143 0.571429 0.585714 0.6 0.614286 0.628571 0.642857 0.657143 0.671429 0.685714 0.7 0.714286 0.728571 0.742857 0.757143 0.771429 0.785714 0.8 0.814286 0.828571 0.842857 0.857143 0.871429 0.885714 0.9 0.914286 0.928571 0.942857 0.957143 0.971429 0.985714 1 1 1 1 1 1
  arc A33 (34.1517, 31.4657) -> (33.1877, 30.8216) centre (54.5011, -0.0327) ccw
  spline S66 degree 5 poles (33.1877, 30.8216) (33.1895, 30.8103) (33.1931, 30.7878) (33.1986, 30.7539) (33.2061, 30.7088) (33.2156, 30.6525) (33.2253, 30.5964) (33.2352, 30.5403) (33.2452, 30.4843) (33.2555, 30.4283) (33.266, 30.3725) (33.2767, 30.3168) (33.2875, 30.2611) (33.2986, 30.2056) (33.3099, 30.1501) (33.3214, 30.0948) (33.3331, 30.0395) (33.3449, 29.9844) (33.357, 29.9293) (33.3693, 29.8744) (33.3819, 29.8195) (33.3946, 29.7648) (33.4075, 29.7101) (33.4206, 29.6556) (33.434, 29.6012) (33.4476, 29.5468) (33.4614, 29.4926) (33.4754, 29.4385) (33.4896, 29.3846) (33.504, 29.3307) (33.5187, 29.2769) (33.5336, 29.2233) (33.5487, 29.1698) (33.5641, 29.1164) (33.5797, 29.0631) (33.5955, 29.01) (33.6116, 28.957) (33.6279, 28.9041) (33.6444, 28.8514) (33.6612, 28.7988) (33.6782, 28.7463) (33.6955, 28.694) (33.713, 28.6418) (33.7308, 28.5898) (33.7488, 28.5379) (33.7672, 28.4861) (33.7857, 28.4345) (33.8046, 28.3831) (33.8237, 28.3318) (33.8431, 28.2807) (33.8628, 28.2298) (33.8828, 28.179) (33.903, 28.1284) (33.9236, 28.078) (33.9444, 28.0278) (33.9634, 27.9829) (33.9784, 27.9481) (33.9892, 27.9233) (33.9957, 27.9085) (33.9979, 27.9037) knots -1 -1 -1 -1 -1 -1 -0.985714 -0.971429 -0.957143 -0.942857 -0.928571 -0.914286 -0.9 -0.885714 -0.871429 -0.857143 -0.842857 -0.828571 -0.814286 -0.8 -0.785714 -0.771429 -0.757143 -0.742857 -0.728571 -0.714286 -0.7 -0.685714 -0.671429 -0.657143 -0.642857 -0.628571 -0.614286 -0.6 -0.585714 -0.571429 -0.557143 -0.542857 -0.528571 -0.514286 -0.5 -0.485714 -0.471429 -0.457143 -0.442857 -0.428571 -0.414286 -0.4 -0.385714 -0.371429 -0.357143 -0.342857 -0.328571 -0.314286 -0.3 -0.285714 -0.271429 -0.257143 -0.242857 -0.228571 -0.221564 -0.221564 -0.221564 -0.221564 -0.221564 -0.221564
  spline S67 degree 3 poles (33.8418, 27.3032) (33.8937, 27.3424) (33.9375, 27.3915) (34.0038, 27.5035) (34.0257, 27.5655) (34.0418, 27.6762) (34.0421, 27.7231) (34.0295, 27.8157) (34.0167, 27.8609) (33.9979, 27.9037) knots 0 0 0 0 0.019532 0.019532 0.039064 0.039064 0.053081 0.053081 0.067098 0.067098 0.067098 0.067098
  arc A34 (33.8418, 27.3032) -> (33.4437, 26.9977) centre (54.5011, -0.0327) ccw
  spline S68 degree 3 poles (32.8232, 27.0023) (32.874, 26.9615) (32.9322, 26.9311) (33.0571, 26.8942) (33.1226, 26.8881) (33.2338, 26.8995) (33.2794, 26.9107) (33.3661, 26.9456) (33.4068, 26.969) (33.4437, 26.9977) knots 0 0 0 0 0.019532 0.019532 0.039064 0.039064 0.053081 0.053081 0.067098 0.067098 0.067098 0.067098
  spline S69 degree 5 poles (32.8232, 27.0023) (32.8191, 27.0056) (32.8065, 27.0158) (32.7854, 27.0326) (32.7556, 27.0561) (32.7172, 27.0861) (32.674, 27.1192) (32.6307, 27.1521) (32.587, 27.1848) (32.5432, 27.2172) (32.4991, 27.2494) (32.4547, 27.2814) (32.4102, 27.3131) (32.3654, 27.3446) (32.3203, 27.3759) (32.2751, 27.407) (32.2296, 27.4379) (32.184, 27.4685) (32.1381, 27.499) (32.092, 27.5292) (32.0458, 27.5592) (31.9993, 27.589) (31.9526, 27.6187) (31.9058, 27.6481) (31.8587, 27.6773) (31.8115, 27.7064) (31.7641, 27.7352) (31.7165, 27.7639) (31.6687, 27.7923) (31.6208, 27.8206) (31.5726, 27.8487) (31.5244, 27.8766) (31.4759, 27.9043) (31.4273, 27.9318) (31.3785, 27.9592) (31.3295, 27.9863) (31.2804, 28.0133) (31.2311, 28.0401) (31.1817, 28.0668) (31.1321, 28.0932) (31.0824, 28.1195) (31.0325, 28.1456) (30.9824, 28.1715) (30.9322, 28.1973) (30.8819, 28.2229) (30.8314, 28.2483) (30.7807, 28.2735) (30.7299, 28.2986) (30.679, 28.3235) (30.6279, 28.3483) (30.5767, 28.3728) (30.5254, 28.3972) (30.4739, 28.4215) (30.4223, 28.4455) (30.3705, 28.4694) (30.3186, 28.4932) (30.277, 28.512) (30.2457, 28.5261) (30.2248, 28.5355) (30.2144, 28.5401) knots 0.221564 0.221564 0.221564 0.221564 0.221564 0.221564 0.228571 0.242857 0.257143 0.271429 0.285714 0.3 0.314286 0.328571 0.342857 0.357143 0.371429 0.385714 0.4 0.414286 0.428571 0.442857 0.457143 0.471429 0.485714 0.5 0.514286 0.528571 0.542857 0.557143 0.571429 0.585714 0.6 0.614286 0.628571 0.642857 0.657143 0.671429 0.685714 0.7 0.714286 0.728571 0.742857 0.757143 0.771429 0.785714 0.8 0.814286 0.828571 0.842857 0.857143 0.871429 0.885714 0.9 0.914286 0.928571 0.942857 0.957143 0.971429 0.985714 1 1 1 1 1 1
  arc A35 (30.2144, 28.5401) -> (29.3427, 27.7757) centre (54.5011, -0.0327) ccw
  spline S70 degree 5 poles (29.3427, 27.7757) (29.346, 27.7648) (29.3525, 27.7428) (29.3624, 27.71) (29.3757, 27.6663) (29.3924, 27.6117) (29.4094, 27.5573) (29.4265, 27.5029) (29.4438, 27.4487) (29.4613, 27.3946) (29.479, 27.3407) (29.4968, 27.2868) (29.5149, 27.2331) (29.5331, 27.1794) (29.5515, 27.1259) (29.5701, 27.0725) (29.5889, 27.0193) (29.6079, 26.9661) (29.6271, 26.9131) (29.6465, 26.8603) (29.666, 26.8075) (29.6858, 26.7549) (29.7057, 26.7024) (29.7259, 26.65) (29.7462, 26.5978) (29.7668, 26.5457) (29.7875, 26.4938) (29.8085, 26.442) (29.8296, 26.3903) (29.851, 26.3388) (29.8726, 26.2874) (29.8943, 26.2362) (29.9163, 26.1851) (29.9385, 26.1342) (29.9609, 26.0834) (29.9835, 26.0328) (30.0064, 25.9824) (30.0294, 25.9321) (30.0527, 25.8819) (30.0762, 25.832) (30.0999, 25.7822) (30.1239, 25.7326) (30.1481, 25.6831) (30.1725, 25.6338) (30.1972, 25.5847) (30.2221, 25.5358) (30.2472, 25.4871) (30.2726, 25.4386) (30.2983, 25.3902) (30.3242, 25.3421) (30.3503, 25.2942) (30.3768, 25.2464) (30.4035, 25.1989) (30.4304, 25.1516) (30.4577, 25.1046) (30.4824, 25.0625) (30.5018, 25.03) (30.5157, 25.0068) (30.5241, 24.993) (30.5269, 24.9885) knots -1 -1 -1 -1 -1 -1 -0.985714 -0.971429 -0.957143 -0.942857 -0.928571 -0.914286 -0.9 -0.885714 -0.871429 -0.857143 -0.842857 -0.828571 -0.814286 -0.8 -0.785714 -0.771429 -0.757143 -0.742857 -0.728571 -0.714286 -0.7 -0.685714 -0.671429 -0.657143 -0.642857 -0.628571 -0.614286 -0.6 -0.585714 -0.571429 -0.557143 -0.542857 -0.528571 -0.514286 -0.5 -0.485714 -0.471429 -0.457143 -0.442857 -0.428571 -0.414286 -0.4 -0.385714 -0.371429 -0.357143 -0.342857 -0.328571 -0.314286 -0.3 -0.285714 -0.271429 -0.257143 -0.242857 -0.228571 -0.221564 -0.221564 -0.221564 -0.221564 -0.221564 -0.221564
  spline S71 degree 3 poles (30.4505, 24.3727) (30.4969, 24.4184) (30.5339, 24.4728) (30.585, 24.5925) (30.5986, 24.6568) (30.6001, 24.7686) (30.5942, 24.8152) (30.5697, 24.9054) (30.5511, 24.9485) (30.5269, 24.9885) knots 0 0 0 0 0.019532 0.019532 0.039064 0.039064 0.053081 0.053081 0.067098 0.067098 0.067098 0.067098
  arc A36 (30.4505, 24.3727) -> (30.0956, 24.0179) centre (54.5011, -0.0327) ccw
  spline S72 degree 3 poles (29.4799, 23.9415) (29.5356, 23.9077) (29.5973, 23.8851) (29.7259, 23.8648) (29.7916, 23.8673) (29.9004, 23.8931) (29.9441, 23.9102) (30.0255, 23.9561) (30.0628, 23.9846) (30.0956, 24.0179) knots 0 0 0 0 0.019532 0.019532 0.039064 0.039064 0.053081 0.053081 0.067098 0.067098 0.067098 0.067098
  spline S73 degree 5 poles (29.4799, 23.9415) (29.4754, 23.9443) (29.4616, 23.9526) (29.4384, 23.9666) (29.4059, 23.986) (29.3638, 24.0107) (29.3167, 24.0379) (29.2694, 24.0649) (29.2219, 24.0916) (29.1742, 24.118) (29.1263, 24.1442) (29.0781, 24.1701) (29.0298, 24.1957) (28.9813, 24.2211) (28.9326, 24.2463) (28.8836, 24.2712) (28.8345, 24.2958) (28.7853, 24.3203) (28.7358, 24.3445) (28.6862, 24.3684) (28.6364, 24.3922) (28.5864, 24.4157) (28.5363, 24.4389) (28.486, 24.462) (28.4355, 24.4848) (28.3849, 24.5075) (28.3342, 24.5299) (28.2832, 24.5521) (28.2322, 24.574) (28.1809, 24.5958) (28.1296, 24.6174) (28.078, 24.6387) (28.0264, 24.6599) (27.9746, 24.6808) (27.9226, 24.7016) (27.8705, 24.7221) (27.8183, 24.7425) (27.766, 24.7626) (27.7135, 24.7826) (27.6609, 24.8023) (27.6081, 24.8219) (27.5552, 24.8413) (27.5022, 24.8604) (27.4491, 24.8794) (27.3958, 24.8982) (27.3424, 24.9168) (27.2889, 24.9352) (27.2353, 24.9535) (27.1816, 24.9715) (27.1277, 24.9894) (27.0737, 25.0071) (27.0196, 25.0245) (26.9654, 25.0419) (26.9111, 25.059) (26.8567, 25.0759) (26.8021, 25.0927) (26.7584, 25.106) (26.7255, 25.1158) (26.7036, 25.1224) (26.6926, 25.1256) knots 0.221564 0.221564 0.221564 0.221564 0.221564 0.221564 0.228571 0.242857 0.257143 0.271429 0.285714 0.3 0.314286 0.328571 0.342857 0.357143 0.371429 0.385714 0.4 0.414286 0.428571 0.442857 0.457143 0.471429 0.485714 0.5 0.514286 0.528571 0.542857 0.557143 0.571429 0.585714 0.6 0.614286 0.628571 0.642857 0.657143 0.671429 0.685714 0.7 0.714286 0.728571 0.742857 0.757143 0.771429 0.785714 0.8 0.814286 0.828571 0.842857 0.857143 0.871429 0.885714 0.9 0.914286 0.928571 0.942857 0.957143 0.971429 0.985714 1 1 1 1 1 1
  arc A37 (26.6926, 25.1256) -> (25.9282, 24.254) centre (54.5011, -0.0327) ccw
  spline S74 degree 5 poles (25.9282, 24.254) (25.9329, 24.2435) (25.9423, 24.2227) (25.9563, 24.1914) (25.9752, 24.1498) (25.9989, 24.0979) (26.0228, 24.0461) (26.0469, 23.9945) (26.0711, 23.943) (26.0955, 23.8917) (26.1201, 23.8404) (26.1448, 23.7894) (26.1698, 23.7384) (26.1948, 23.6877) (26.2201, 23.637) (26.2455, 23.5865) (26.2711, 23.5362) (26.2968, 23.486) (26.3228, 23.4359) (26.3489, 23.386) (26.3751, 23.3363) (26.4016, 23.2867) (26.4282, 23.2372) (26.455, 23.188) (26.482, 23.1388) (26.5092, 23.0899) (26.5366, 23.0411) (26.5641, 22.9925) (26.5918, 22.944) (26.6197, 22.8957) (26.6478, 22.8476) (26.6761, 22.7997) (26.7045, 22.7519) (26.7332, 22.7043) (26.762, 22.6569) (26.791, 22.6097) (26.8203, 22.5626) (26.8497, 22.5158) (26.8793, 22.4691) (26.9092, 22.4226) (26.9392, 22.3763) (26.9694, 22.3303) (26.9999, 22.2844) (27.0305, 22.2387) (27.0614, 22.1933) (27.0924, 22.148) (27.1237, 22.103) (27.1552, 22.0582) (27.187, 22.0136) (27.2189, 21.9693) (27.2511, 21.9252) (27.2836, 21.8813) (27.3162, 21.8377) (27.3491, 21.7943) (27.3823, 21.7512) (27.4123, 21.7127) (27.4358, 21.683) (27.4526, 21.6619) (27.4627, 21.6493) (27.4661, 21.6451) knots -1 -1 -1 -1 -1 -1 -0.985714 -0.971429 -0.957143 -0.942857 -0.928571 -0.914286 -0.9 -0.885714 -0.871429 -0.857143 -0.842857 -0.828571 -0.814286 -0.8 -0.785714 -0.771429 -0.757143 -0.742857 -0.728571 -0.714286 -0.7 -0.685714 -0.671429 -0.657143 -0.642857 -0.628571 -0.614286 -0.6 -0.585714 -0.571429 -0.557143 -0.542857 -0.528571 -0.514286 -0.5 -0.485714 -0.471429 -0.457143 -0.442857 -0.428571 -0.414286 -0.4 -0.385714 -0.371429 -0.357143 -0.342857 -0.328571 -0.314286 -0.3 -0.285714 -0.271429 -0.257143 -0.242857 -0.228571 -0.221564 -0.221564 -0.221564 -0.221564 -0.221564 -0.221564
  spline S75 degree 3 poles (27.4707, 21.0247) (27.5107, 21.0761) (27.5403, 21.1348) (27.5753, 21.2602) (27.5804, 21.3257) (27.5674, 21.4368) (27.5554, 21.4822) (27.5193, 21.5684) (27.4953, 21.6087) (27.4661, 21.6451) knots 0 0 0 0 0.019532 0.019532 0.039064 0.039064 0.053081 0.053081 0.067098 0.067098 0.067098 0.067098
  arc A38 (27.4707, 21.0247) -> (27.1652, 20.6266) centre (54.5011, -0.0327) ccw
  spline S76 degree 3 poles (26.5647, 20.4705) (26.6243, 20.4442) (26.6884, 20.4299) (26.8186, 20.4265) (26.8834, 20.4376) (26.9879, 20.4774) (27.029, 20.5001) (27.1038, 20.5562) (27.137, 20.5893) (27.1652, 20.6266) knots 0 0 0 0 0.019532 0.019532 0.039064 0.039064 0.053081 0.053081 0.067098 0.067098 0.067098 0.067098
  spline S77 degree 5 poles (26.5647, 20.4705) (26.5598, 20.4726) (26.5451, 20.4791) (26.5203, 20.4899) (26.4855, 20.5049) (26.4406, 20.5239) (26.3903, 20.5448) (26.3399, 20.5654) (26.2893, 20.5856) (26.2386, 20.6056) (26.1876, 20.6253) (26.1365, 20.6447) (26.0853, 20.6638) (26.0338, 20.6826) (25.9823, 20.7012) (25.9305, 20.7195) (25.8786, 20.7376) (25.8266, 20.7553) (25.7744, 20.7729) (25.7221, 20.7902) (25.6696, 20.8072) (25.617, 20.824) (25.5642, 20.8405) (25.5114, 20.8568) (25.4584, 20.8729) (25.4052, 20.8887) (25.352, 20.9043) (25.2986, 20.9196) (25.2451, 20.9347) (25.1914, 20.9496) (25.1377, 20.9643) (25.0838, 20.9788) (25.0298, 20.993) (24.9757, 21.007) (24.9215, 21.0208) (24.8672, 21.0344) (24.8128, 21.0477) (24.7582, 21.0609) (24.7036, 21.0738) (24.6489, 21.0865) (24.594, 21.099) (24.539, 21.1113) (24.484, 21.1234) (24.4288, 21.1353) (24.3736, 21.147) (24.3182, 21.1585) (24.2628, 21.1697) (24.2072, 21.1808) (24.1516, 21.1917) (24.0959, 21.2024) (24.04, 21.2129) (23.9841, 21.2231) (23.9281, 21.2332) (23.872, 21.2431) (23.8158, 21.2528) (23.7596, 21.2623) (23.7145, 21.2697) (23.6806, 21.2752) (23.658, 21.2789) (23.6467, 21.2807) knots 0.221564 0.221564 0.221564 0.221564 0.221564 0.221564 0.228571 0.242857 0.257143 0.271429 0.285714 0.3 0.314286 0.328571 0.342857 0.357143 0.371429 0.385714 0.4 0.414286 0.428571 0.442857 0.457143 0.471429 0.485714 0.5 0.514286 0.528571 0.542857 0.557143 0.571429 0.585714 0.6 0.614286 0.628571 0.642857 0.657143 0.671429 0.685714 0.7 0.714286 0.728571 0.742857 0.757143 0.771429 0.785714 0.8 0.814286 0.828571 0.842857 0.857143 0.871429 0.885714 0.9 0.914286 0.928571 0.942857 0.957143 0.971429 0.985714 1 1 1 1 1 1
  arc A39 (23.6467, 21.2807) -> (23.0026, 20.3167) centre (54.5011, -0.0327) ccw
  spline S78 degree 5 poles (23.0026, 20.3167) (23.0086, 20.307) (23.0206, 20.2875) (23.0387, 20.2583) (23.0628, 20.2195) (23.0931, 20.1712) (23.1236, 20.123) (23.1542, 20.0749) (23.1849, 20.027) (23.2158, 19.9793) (23.2468, 19.9317) (23.278, 19.8843) (23.3094, 19.8371) (23.3409, 19.79) (23.3725, 19.7431) (23.4043, 19.6964) (23.4362, 19.6498) (23.4683, 19.6034) (23.5006, 19.5571) (23.533, 19.5111) (23.5655, 19.4652) (23.5982, 19.4195) (23.6311, 19.3739) (23.6641, 19.3286) (23.6972, 19.2834) (23.7306, 19.2384) (23.7641, 19.1936) (23.7977, 19.149) (23.8315, 19.1046) (23.8655, 19.0603) (23.8996, 19.0163) (23.9339, 18.9724) (23.9683, 18.9288) (24.003, 18.8853) (24.0377, 18.8421) (24.0727, 18.7991) (24.1078, 18.7562) (24.1431, 18.7136) (24.1786, 18.6712) (24.2142, 18.629) (24.25, 18.5871) (24.286, 18.5453) (24.3222, 18.5038) (24.3585, 18.4626) (24.395, 18.4215) (24.4318, 18.3807) (24.4687, 18.3402) (24.5057, 18.2999) (24.543, 18.2598) (24.5805, 18.22) (24.6182, 18.1805) (24.6561, 18.1413) (24.6941, 18.1023) (24.7324, 18.0636) (24.7709, 18.0251) (24.8057, 17.9909) (24.8328, 17.9645) (24.8523, 17.9458) (24.864, 17.9346) (24.8678, 17.9309) knots -1 -1 -1 -1 -1 -1 -0.985714 -0.971429 -0.957143 -0.942857 -0.928571 -0.914286 -0.9 -0.885714 -0.871429 -0.857143 -0.842857 -0.828571 -0.814286 -0.8 -0.785714 -0.771429 -0.757143 -0.742857 -0.728571 -0.714286 -0.7 -0.685714 -0.671429 -0.657143 -0.642857 -0.628571 -0.614286 -0.6 -0.585714 -0.571429 -0.557143 -0.542857 -0.528571 -0.514286 -0.5 -0.485714 -0.471429 -0.457143 -0.442857 -0.428571 -0.414286 -0.4 -0.385714 -0.371429 -0.357143 -0.342857 -0.328571 -0.314286 -0.3 -0.285714 -0.271429 -0.257143 -0.242857 -0.228571 -0.221564 -0.221564 -0.221564 -0.221564 -0.221564 -0.221564
  spline S79 degree 3 poles (24.9534, 17.3164) (24.9864, 17.3725) (25.008, 17.4346) (25.0264, 17.5635) (25.0229, 17.6291) (24.9955, 17.7375) (24.9777, 17.781) (24.9307, 17.8617) (24.9016, 17.8986) (24.8678, 17.9309) knots 0 0 0 0 0.019532 0.019532 0.039064 0.039064 0.053081 0.053081 0.067098 0.067098 0.067098 0.067098
  arc A40 (24.9534, 17.3164) -> (24.7025, 16.8818) centre (54.5011, -0.0327) ccw
  spline S80 degree 3 poles (24.1275, 16.6487) (24.19, 16.6304) (24.2555, 16.6245) (24.385, 16.6382) (24.4478, 16.6577) (24.5462, 16.7108) (24.584, 16.7386) (24.6508, 16.804) (24.6794, 16.8412) (24.7025, 16.8818) knots 0 0 0 0 0.019532 0.019532 0.039064 0.039064 0.053081 0.053081 0.067098 0.067098 0.067098 0.067098